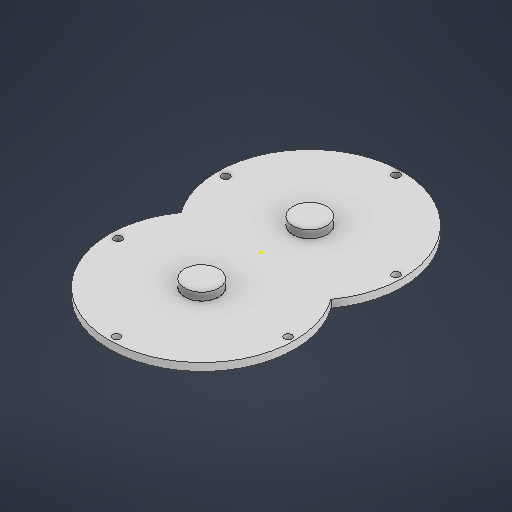
# Autodesk Inventor part: tapa
Saved by Autodesk Inventor 2026.2 (Build 302298000, 298)
## iProperties
Created: 2026-10-09
Part Number: tapa
Material: Genérico
Document SubType Name: Modeling
Designer: IFSP
Density: 1 g/cm^3
Appearance: Padrão
Author: IFSP
Autodesk Inventor part; units mm, degrees
ref_plane "YZ Plane" through (0, 0, 0) normal (1, 0, 0) x (0, 1, 0)
ref_plane "XZ Plane" through (0, 0, 0) normal (0, 1, 0) x (-1, 0, 0)
ref_plane "XY Plane" through (0, 0, 0) normal (0, 0, 1) x (1, 0, 0)
sketch "Esboço1" plane through (0, 0, 0) normal (0, 1, 0) x (-1, 0, 0)
  line L0 (0, 38.1159) -> (0, -31.8841) construction
  circle A0 centre (0, 38.1159) radius 11
  circle A1 centre (0, -31.8841) radius 11
  arc A2 (-48.734, 3.1159) -> (48.734, 3.1159) centre (0, -31.8841) ccw
  arc A3 (48.734, 3.1159) -> (-48.734, 3.1159) centre (0, 38.1159) ccw
  circle A4 centre (54.5817, 38.1159) radius 2.5
  circle A5 centre (54.5817, -31.8841) radius 2.5
  line L1 (54.5817, 38.1159) -> (54.5817, -31.8841) construction
  line L2 (54.5817, 38.1159) -> (0, 38.1159) construction
  line L3 (54.5817, -31.8841) -> (0, -31.8841) construction
  line L4 (54.5817, 38.1159) -> (-15.4183, 38.1159) construction
  line L5 (-15.4183, 38.1159) -> (-85.4183, 38.1159) construction
  line L6 (0, -31.8841) -> (-87.9847, -31.8841) construction
  circle A6 centre (-55.9371, 38.1159) radius 2.5
  circle A7 centre (-55.9371, -31.8841) radius 2.5
  circle A8 centre (0, 93.7435) radius 2.5
  circle A9 centre (0, -87.7828) radius 2.5
  circle A10 centre (0, 38.1159) radius 5
  circle A11 centre (0, -31.8841) radius 5
  point P0 (0, 0)
  dimension "d0" = 70
  dimension "d4" = 22
  dimension "d11" = 70
  dimension "d14" = 70
  dimension "d15" = 70
  dimension "d16" = 5
  dimension "d17" = 5
  dimension "d18" = 5
  dimension "d19" = 5
  dimension "d20" = 10
  dimension "d21" = 10
  constraints: 14 end point, 12 centre point, 6 coincident, 4 point on circle, 4 point on line, 2 vertical, 1 horizontal, 1 perpendicular
  measures "d0" distance of L0.start L0.end
  measures "d4" diameter of A1
  measures "d11" distance of L1.start L1.end
  measures "d14" distance of L1.start L4.end
  measures "d15" distance of L4.end L5.end
  measures "d16" diameter of A6
  measures "d17" diameter of A7
  measures "d18" diameter of A8
  measures "d19" diameter of A9
  measures "d20" diameter of A10
  measures "d21" diameter of A11
extrude "Extrusão1" add sketch "Esboço1" against normal blind 5 contours A3 A2
sketch "Esboço2" plane through (0, 0, 0) normal (0, 1, 0) x (1, 0, 0)
  point P0 (0, 0)
sketch "Esboço3" plane through (0, 0, 0) normal (0, 1, 0) x (1, 0, 0)
  circle A0 centre (0, -38.3898) radius 11
  circle A1 centre (0, 31.7831) radius 11
  circle A2 centre (0, -38.3898) radius 5
  circle A3 centre (0, 31.7831) radius 5
  point P0 (0, 0)
  dimension "d24" = 22
  dimension "d25" = 22
  dimension "d26" = 10
  dimension "d27" = 10
  constraints: 4 centre point, 2 coincident
  measures "d24" diameter of A0
  measures "d25" diameter of A1
  measures "d26" diameter of A2
  measures "d27" diameter of A3
extrude "Extrusão2" add sketch "Esboço3" along normal blind 5 contours A0 | A1 | A2 | A3
sketch "Esboço4" plane through (0, -5, 0) normal (0, -1, 0) x (1, 0, 0)
  point P0 (0, 0)
